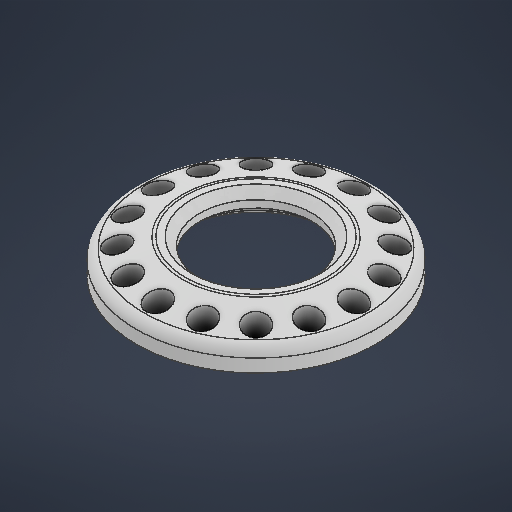
# Autodesk Inventor part: OUTPUT_D
Saved by Autodesk Inventor 2026.2 (Build 302298010, 298A)
## iProperties
Created: 2026-04-06
Part Number: OUTPUT_D
Material: 일반
Document SubType Name: Modeling
Designer: work
Density: 1 g/cm^3
Appearance: 기본값
Author: work
Autodesk Inventor part; units mm, degrees
ref_plane "YZ Plane" through (0, 0, 0) normal (1, 0, 0) x (0, 1, 0)
ref_plane "XZ Plane" through (0, 0, 0) normal (0, 1, 0) x (-1, 0, 0)
ref_plane "XY Plane" through (0, 0, 0) normal (0, 0, 1) x (1, 0, 0)
sketch "스케치1" plane through (0, 0, 0) normal (0, 1, 0) x (-1, 0, 0)
  circle A0 centre (0, 0) radius 18.5 construction
  line L0 (0, 0) -> (18.5, 0) construction
  circle A1 centre (0, 0) radius 22.5
  circle A2 centre (18.5, 0) radius 2.1
  circle A3 centre (17.0918, 7.0796) radius 2.1
  circle A4 centre (13.0815, 13.0815) radius 2.1
  circle A5 centre (7.0796, 17.0918) radius 2.1
  circle A6 centre (0, 18.5) radius 2.1
  circle A7 centre (-7.0796, 17.0918) radius 2.1
  circle A8 centre (-13.0815, 13.0815) radius 2.1
  circle A9 centre (-17.0918, 7.0796) radius 2.1
  circle A10 centre (-18.5, 0) radius 2.1
  circle A11 centre (-17.0918, -7.0796) radius 2.1
  circle A12 centre (-13.0815, -13.0815) radius 2.1
  circle A13 centre (-7.0796, -17.0918) radius 2.1
  circle A14 centre (0, -18.5) radius 2.1
  circle A15 centre (7.0796, -17.0918) radius 2.1
  circle A16 centre (13.0815, -13.0815) radius 2.1
  circle A17 centre (17.0918, -7.0796) radius 2.1
  circle A18 centre (0, 0) radius 13.6
  dimension "d0" = 37
  dimension "d1" = 45
  dimension "d2" = 4.2
  dimension "d5" = 360
  dimension "d7" = 27.2
  constraints: 18 centre point, 4 coincident, 2 end point, 1 horizontal, 1 horizontal alignment, 35 other
  measures "d1" diameter of A1
  measures "d2" diameter of A2
  measures "d7" diameter of A18
extrude "돌출1" add sketch "스케치1" along normal blind 10
sketch "스케치2" plane through (0, 0, 0) normal (1, 0, 0) x (0, 1, 0)
  line L0 (0, 0) -> (10, 0)
  line L1 (10, 13.6) -> (10, -13.6) projected
  line L2 (10, 0) -> (3.9711, -22.5)
  line L3 (0, -22.5) -> (10, -22.5) projected
  line L4 (10, -13.6) -> (10, -22.5)
  line L5 (10, -10.9815) -> (10, -15.1815) projected
  dimension "d16" = 75
  constraints: 6 end point, 1 collinear, 1 midpoint, 1 point on line
  measures "d16" angle of L0 L2
sketch "스케치4" plane through (0, 0, 0) normal (0, 0, 1) x (1, 0, 0)
  line L0 (16.4, 10) -> (20.6, 10) projected
  line L1 (18.5, 10) -> (18.5, 0)
  line L2 (14.9918, 0) -> (19.1918, 0) projected
  line L3 (22.5, 10) -> (-22.5, 10) projected
  line L4 (20.8992, 10) -> (20.55, 0)
  line L5 (18.5, 0) -> (20.55, 0)
  point P0 (0, 0)
  dimension "d10" = 2
  dimension "d11" = 2.05
  constraints: 6 end point, 2 point on line, 1 horizontal, 1 midpoint, 1 vertical
  measures "d10" angle of L1 L4
  measures "d11" distance from line of L1 L4.end
revolve "회전1" cut sketch "스케치4" angle 360 about axis through (18.5, 10, 0) along (0, -1, 0)
pattern_circular "원형 패턴1" count 16 over 360 about axis through (0, -10, 0) along (0, 1, 0) of "회전1"
revolve "회전2" cut sketch "스케치2" angle 360 about axis through (0, 0, 0) along (0, 1, 0)
sketch "스케치5" plane through (0, 0, 0) normal (0, 0, 1) x (1, 0, 0)
  line L0 (13.6, 6.3559) -> (-13.6, 6.3559) projected
  line L1 (10.6, 6.3559) -> (10.6, 3.5)
  line L2 (10.6, 3.5) -> (13.6, 3.5)
  line L3 (-13.6, 0) -> (13.6, 0) projected
  line L4 (13.6, 6.3559) -> (13.6, 0) projected
  line L5 (0, 6.3559) -> (0, 0)
  dimension "d19" = 3.5
  dimension "d20" = 3
  constraints: 6 end point, 2 perpendicular, 2 point on line, 1 midpoint, 1 vertical
  measures "d19" distance between parallel lines of L3 L2
  measures "d20" distance between parallel lines of L4 L1
revolve "회전3" add sketch "스케치5" angle 360 about axis through (0, 6.3559, 0) along (0, -1, 0) contours L4 L2 L1 L0
fillet "모깎기1" radius 0.75 1 edges at (13.6, 3.5, 0)
chamfer "모따기1" distance 1.5 angle 45 1 edges at (-10.6, 6.3559, 0)
fillet "모깎기2" radius 2 3 edges at (0, 6.3559, 13.6) (15.9099, 3.9711, 15.9099) (-15.9099, 3.9711, -15.9099)
chamfer "모따기2" distance 1 angle 45 1 edges at (13.6, 0, 0)
